Autodesk Fusion 360 part; units mm, degrees
(part 2 of 3)
extrude "Diffuser open rear skirt" add sketch "Diffuser hollow skirt outside profile" against normal blind 2.6 bodies 4
ref_plane "WorkPlane13" through (12.125, -2.4482, 27.9828) normal (0, -0.087156, 0.996195) x (1, 0, 0)
sketch "Diffuser optical cavity profile" plane through (0, -2.4482, 27.9828) normal (0, -0.087156, 0.996195) x (1, 0, 0)
  line L0 (7.7, 94.1972) -> (72.3, 94.1972)
  line L1 (72.3, 94.1972) -> (72.3, 101.7972)
  line L2 (72.3, 101.7972) -> (7.7, 101.7972)
  line L3 (7.7, 101.7972) -> (7.7, 94.1972)
  dimension "d533" = 7.7
  dimension "d534" = 94.1972
  dimension "d535" = 64.6
  dimension "d536" = 7.6
  constraint horizontal L0
  constraint vertical L1
  constraint horizontal L2
  constraint vertical L3
  measures "d533" horizontal distance of origin L0.start
  measures "d534" vertical distance of origin L0.start
  measures "d535" distance of L0.start L0.end
  measures "d536" distance of L0.end L1.end
extrude "Hollow diffuser from inside" cut sketch "Diffuser optical cavity profile" against normal blind 7 bodies 4
sketch "Diffuser right wire exit profile" plane through (0, -2.2216, 25.3927) normal (0, -0.087156, 0.996195) x (1, 0, 0)
  line L0 (71.5, 95.9972) -> (76.5, 95.9972)
  line L1 (76.5, 95.9972) -> (76.5, 99.9972)
  line L2 (76.5, 99.9972) -> (71.5, 99.9972)
  line L3 (71.5, 99.9972) -> (71.5, 95.9972)
  dimension "d539" = 71.5
  dimension "d540" = 95.9972
  dimension "d541" = 5
  dimension "d542" = 4
  constraint horizontal L0
  constraint vertical L1
  constraint horizontal L2
  constraint vertical L3
  measures "d539" horizontal distance of origin L0.start
  measures "d540" vertical distance of origin L0.start
  measures "d541" distance of L0.start L0.end
  measures "d542" distance of L0.end L1.end
extrude "Diffuser right wire exit" cut sketch "Diffuser right wire exit profile" against normal blind 6 bodies 4
sketch "Deep diffuser skirt clearance profile" plane through (0, -2.2739, 25.9904) normal (0, -0.087156, 0.996195) x (1, 0, 0)
  line L0 (5, 91.4972) -> (75, 91.4972)
  line L1 (75, 91.4972) -> (75, 104.4972)
  line L2 (75, 104.4972) -> (5, 104.4972)
  line L3 (5, 104.4972) -> (5, 91.4972)
  dimension "d545" = 5
  dimension "d546" = 91.4972
  dimension "d547" = 70
  dimension "d548" = 13
  constraint horizontal L0
  constraint vertical L1
  constraint horizontal L2
  constraint vertical L3
  measures "d545" horizontal distance of origin L0.start
  measures "d546" vertical distance of origin L0.start
  measures "d547" distance of L0.start L0.end
  measures "d548" distance of L0.end L1.end
extrude "Clear carrier around hollow diffuser" cut sketch "Deep diffuser skirt clearance profile" against normal blind 3.4 bodies 2
sketch "LED rear support web profile" plane through (0, -2.2739, 25.9904) normal (0, -0.087156, 0.996195) x (1, 0, 0)
  line L0 (6.3, 108.1799) -> (73.7, 108.1799)
  line L1 (73.7, 108.1799) -> (73.7, 112.1799)
  line L2 (73.7, 112.1799) -> (6.3, 112.1799)
  line L3 (6.3, 112.1799) -> (6.3, 108.1799)
  dimension "d551" = 6.3
  dimension "d552" = 108.1799
  dimension "d553" = 67.4
  dimension "d554" = 4
  constraint horizontal L0
  constraint vertical L1
  constraint horizontal L2
  constraint vertical L3
  measures "d551" horizontal distance of origin L0.start
  measures "d552" vertical distance of origin L0.start
  measures "d553" distance of L0.start L0.end
  measures "d554" distance of L0.end L1.end
extrude "LED rear support web" add sketch "LED rear support web profile" against normal blind 5.8 bodies 2
ref_plane "WorkPlane14" through (12.125, -1.9775, 22.6033) normal (0, -0.087156, 0.996195) x (1, 0, 0)
sketch "Continuous LED tray profile" plane through (0, -1.9775, 22.6033) normal (0, -0.087156, 0.996195) x (1, 0, 0)
  line L0 (6.3, 92.7972) -> (73.7, 92.7972)
  line L1 (73.7, 92.7972) -> (73.7, 114.4037)
  line L2 (73.7, 114.4037) -> (6.3, 114.4037)
  line L3 (6.3, 114.4037) -> (6.3, 92.7972)
  dimension "d559" = 6.3
  dimension "d560" = 92.7972
  dimension "d561" = 67.4
  dimension "d562" = 21.6065
  constraint horizontal L0
  constraint vertical L1
  constraint horizontal L2
  constraint vertical L3
  measures "d559" horizontal distance of origin L0.start
  measures "d560" vertical distance of origin L0.start
  measures "d561" distance of L0.start L0.end
  measures "d562" distance of L0.end L1.end
extrude "Continuous LED mounting crossbar" add sketch "Continuous LED tray profile" against normal blind 2.4 bodies 2
sketch "LED tray right wire relief profile" plane through (0, -1.9775, 22.6033) normal (0, -0.087156, 0.996195) x (1, 0, 0)
  line L0 (71.5, 95.9972) -> (75.5, 95.9972)
  line L1 (75.5, 95.9972) -> (75.5, 99.9972)
  line L2 (75.5, 99.9972) -> (71.5, 99.9972)
  line L3 (71.5, 99.9972) -> (71.5, 95.9972)
  dimension "d565" = 71.5
  dimension "d566" = 95.9972
  dimension "d567" = 4
  dimension "d568" = 4
  constraint horizontal L0
  constraint vertical L1
  constraint horizontal L2
  constraint vertical L3
  measures "d565" horizontal distance of origin L0.start
  measures "d566" vertical distance of origin L0.start
  measures "d567" distance of L0.start L0.end
  measures "d568" distance of L0.end L1.end
extrude "LED tray right wire relief" cut sketch "LED tray right wire relief profile" against normal blind 3.4 bodies 2
sketch "OLED seat 1 profile" plane through (0, -2.5179, 28.7797) normal (0, -0.087156, 0.996195) x (1, 0, 0)
  line L0 (5.75, 59.4972) -> (41.75, 59.4972)
  line L1 (41.75, 59.4972) -> (41.75, 62.4972)
  line L2 (41.75, 62.4972) -> (5.75, 62.4972)
  line L3 (5.75, 62.4972) -> (5.75, 59.4972)
  dimension "d571" = 5.75
  dimension "d572" = 59.4972
  dimension "d573" = 36
  dimension "d574" = 3
  constraint horizontal L0
  constraint vertical L1
  constraint horizontal L2
  constraint vertical L3
  measures "d571" horizontal distance of origin L0.start
  measures "d572" vertical distance of origin L0.start
  measures "d573" distance of L0.start L0.end
  measures "d574" distance of L0.end L1.end
extrude "OLED opposed locating ledge 1" add sketch "OLED seat 1 profile" against normal blind 2.8 bodies 1
sketch "OLED seat 2 profile" plane through (0, -2.5179, 28.7797) normal (0, -0.087156, 0.996195) x (1, 0, 0)
  line L0 (5.75, 88.4972) -> (41.75, 88.4972)
  line L1 (41.75, 88.4972) -> (41.75, 91.4972)
  line L2 (41.75, 91.4972) -> (5.75, 91.4972)
  line L3 (5.75, 91.4972) -> (5.75, 88.4972)
  dimension "d577" = 5.75
  dimension "d578" = 88.4972
  dimension "d579" = 36
  dimension "d580" = 3
  constraint horizontal L0
  constraint vertical L1
  constraint horizontal L2
  constraint vertical L3
  measures "d577" horizontal distance of origin L0.start
  measures "d578" vertical distance of origin L0.start
  measures "d579" distance of L0.start L0.end
  measures "d580" distance of L0.end L1.end
extrude "OLED opposed locating ledge 2" add sketch "OLED seat 2 profile" against normal blind 2.8 bodies 1
sketch "OLED PCB carrier clearance profile" plane through (0, -2.2739, 25.9904) normal (0, -0.087156, 0.996195) x (1, 0, 0)
  line L0 (5.55, 59.2972) -> (41.95, 59.2972)
  line L1 (41.95, 59.2972) -> (41.95, 93.6972)
  line L2 (41.95, 93.6972) -> (5.55, 93.6972)
  line L3 (5.55, 93.6972) -> (5.55, 59.2972)
  dimension "d583" = 5.55
  dimension "d584" = 59.2972
  dimension "d585" = 36.4
  dimension "d586" = 34.4
  constraint horizontal L0
  constraint vertical L1
  constraint horizontal L2
  constraint vertical L3
  measures "d583" horizontal distance of origin L0.start
  measures "d584" vertical distance of origin L0.start
  measures "d585" distance of L0.start L0.end
  measures "d586" distance of L0.end L1.end
extrude "OLED PCB clearance in carrier" cut sketch "OLED PCB carrier clearance profile" against normal blind 1.8 bodies 2
ref_plane "WorkPlane15" through (12.125, -2.117, 24.1972) normal (0, -0.087156, 0.996195) x (1, 0, 0)
sketch "OLED front clamp root profile" plane through (0, -2.2739, 25.9904) normal (0, -0.087156, 0.996195) x (1, 0, 0)
  line L0 (18, 58.4972) -> (32, 58.4972)
  line L1 (32, 58.4972) -> (32, 59.4972)
  line L2 (32, 59.4972) -> (18, 59.4972)
  line L3 (18, 59.4972) -> (18, 58.4972)
  dimension "d591" = 18
  dimension "d592" = 58.4972
  dimension "d593" = 14
  dimension "d594" = 1
  constraint horizontal L0
  constraint vertical L1
  constraint horizontal L2
  constraint vertical L3
  measures "d591" horizontal distance of origin L0.start
  measures "d592" vertical distance of origin L0.start
  measures "d593" distance of L0.start L0.end
  measures "d594" distance of L0.end L1.end
extrude "OLED front clamp root" add sketch "OLED front clamp root profile" against normal blind 3.8 bodies 2
sketch "OLED front opposed clamp profile" plane through (0, -2.117, 24.1972) normal (0, -0.087156, 0.996195) x (1, 0, 0)
  line L0 (18, 58.4972) -> (32, 58.4972)
  line L1 (32, 58.4972) -> (32, 62.4972)
  line L2 (32, 62.4972) -> (18, 62.4972)
  line L3 (18, 62.4972) -> (18, 58.4972)
  dimension "d597" = 18
  dimension "d598" = 58.4972
  dimension "d599" = 14
  dimension "d600" = 4
  constraint horizontal L0
  constraint vertical L1
  constraint horizontal L2
  constraint vertical L3
  measures "d597" horizontal distance of origin L0.start
  measures "d598" vertical distance of origin L0.start
  measures "d599" distance of L0.start L0.end
  measures "d600" distance of L0.end L1.end
extrude "OLED front opposed clamp" add sketch "OLED front opposed clamp profile" against normal blind 2 bodies 2
sketch "OLED rear clamp connecting bridge profile" plane through (0, -1.9775, 22.6033) normal (0, -0.087156, 0.996195) x (1, 0, 0)
  line L0 (18, 89.2972) -> (32, 89.2972)
  line L1 (32, 89.2972) -> (32, 93.0972)
  line L2 (32, 93.0972) -> (18, 93.0972)
  line L3 (18, 93.0972) -> (18, 89.2972)
  dimension "d603" = 18
  dimension "d604" = 89.2972
  dimension "d605" = 14
  dimension "d606" = 3.8
  constraint horizontal L0
  constraint vertical L1
  constraint horizontal L2
  constraint vertical L3
  measures "d603" horizontal distance of origin L0.start
  measures "d604" vertical distance of origin L0.start
  measures "d605" distance of L0.start L0.end
  measures "d606" distance of L0.end L1.end
extrude "OLED rear clamp connecting bridge" add sketch "OLED rear clamp connecting bridge profile" against normal blind 2.4 bodies 2
sketch "OLED rear opposed clamp profile" plane through (0, -2.117, 24.1972) normal (0, -0.087156, 0.996195) x (1, 0, 0)
  line L0 (18, 89.4972) -> (32, 89.4972)
  line L1 (32, 89.4972) -> (32, 91.4972)
  line L2 (32, 91.4972) -> (18, 91.4972)
  line L3 (18, 91.4972) -> (18, 89.4972)
  dimension "d609" = 18
  dimension "d610" = 89.4972
  dimension "d611" = 14
  dimension "d612" = 2
  constraint horizontal L0
  constraint vertical L1
  constraint horizontal L2
  constraint vertical L3
  measures "d609" horizontal distance of origin L0.start
  measures "d610" vertical distance of origin L0.start
  measures "d611" distance of L0.start L0.end
  measures "d612" distance of L0.end L1.end
extrude "OLED rear opposed clamp" add sketch "OLED rear opposed clamp profile" against normal blind 2 bodies 2
sketch "OLED PCB carrier clearance profile (1)" plane through (0, -2.2739, 25.9904) normal (0, -0.087156, 0.996195) x (1, 0, 0)
  line L0 (5.55, 59.2972) -> (41.95, 59.2972)
  line L1 (41.95, 59.2972) -> (41.95, 93.6972)
  line L2 (41.95, 93.6972) -> (5.55, 93.6972)
  line L3 (5.55, 93.6972) -> (5.55, 59.2972)
  dimension "d615" = 5.55
  dimension "d616" = 59.2972
  dimension "d617" = 36.4
  dimension "d618" = 34.4
  constraint horizontal L0
  constraint vertical L1
  constraint horizontal L2
  constraint vertical L3
  measures "d615" horizontal distance of origin L0.start
  measures "d616" vertical distance of origin L0.start
  measures "d617" distance of L0.start L0.end
  measures "d618" distance of L0.end L1.end
extrude "OLED PCB clearance in carrier (1)" cut sketch "OLED PCB carrier clearance profile (1)" against normal blind 1.8 bodies 2
ref_plane "WorkPlane16" through (0, 0, 26.3) normal (0, 0, 1) x (1, 0, 0)
sketch "PCB1 perimeter support profile" plane through (0, 0, 26.3) normal (0, 0, 1) x (1, 0, 0)
  line L0 (3.2, 62.2) -> (4.8, 62.2)
  line L1 (4.8, 62.2) -> (4.8, 66.2)
  line L2 (4.8, 66.2) -> (3.2, 66.2)
  line L3 (3.2, 66.2) -> (3.2, 62.2)
  dimension "d623" = 3.2
  dimension "d624" = 62.2
  dimension "d625" = 1.6
  dimension "d626" = 4
  constraint horizontal L0
  constraint vertical L1
  constraint horizontal L2
  constraint vertical L3
  measures "d623" horizontal distance of origin L0.start
  measures "d624" vertical distance of origin L0.start
  measures "d625" distance of L0.start L0.end
  measures "d626" distance of L0.end L1.end
sketch "PCB1 short post bridge profile" plane through (0, 0, 26.3) normal (0, 0, 1) x (1, 0, 0)
  line L0 (3.2, 62.2) -> (7, 62.2)
  line L1 (7, 62.2) -> (7, 66.2)
  line L2 (7, 66.2) -> (3.2, 66.2)
  line L3 (3.2, 66.2) -> (3.2, 62.2)
  dimension "d629" = 3.2
  dimension "d630" = 62.2
  dimension "d631" = 3.8
  dimension "d632" = 4
  constraint horizontal L0
  constraint vertical L1
  constraint horizontal L2
  constraint vertical L3
  measures "d629" horizontal distance of origin L0.start
  measures "d630" vertical distance of origin L0.start
  measures "d631" distance of L0.start L0.end
  measures "d632" distance of L0.end L1.end
sketch "PCB1 post profile" plane through (0, 0, 22.3) normal (0, 0, 1) x (1, 0, 0)
  circle A0 centre (7, 64.2) radius 2.2
  dimension "d635" = 7
  dimension "d636" = 64.2
  dimension "d637" = 4.4
  measures "d635" horizontal distance of origin A0.centre
  measures "d636" vertical distance of origin A0.centre
  measures "d637" diameter of A0
sketch "PCB1 M2 pilot profile" plane through (0, 0, 22.3) normal (0, 0, 1) x (1, 0, 0)
  circle A0 centre (7, 64.2) radius 0.85
  dimension "d640" = 7
  dimension "d641" = 64.2
  dimension "d642" = 1.7
  measures "d640" horizontal distance of origin A0.centre
  measures "d641" vertical distance of origin A0.centre
  measures "d642" diameter of A0
sketch "PCB2 perimeter support profile" plane through (0, 0, 26.3) normal (0, 0, 1) x (1, 0, 0)
  line L0 (75.2, 62.2) -> (76.8, 62.2)
  line L1 (76.8, 62.2) -> (76.8, 66.2)
  line L2 (76.8, 66.2) -> (75.2, 66.2)
  line L3 (75.2, 66.2) -> (75.2, 62.2)
  dimension "d645" = 75.2
  dimension "d646" = 62.2
  dimension "d647" = 1.6
  dimension "d648" = 4
  constraint horizontal L0
  constraint vertical L1
  constraint horizontal L2
  constraint vertical L3
  measures "d645" horizontal distance of origin L0.start
  measures "d646" vertical distance of origin L0.start
  measures "d647" distance of L0.start L0.end
  measures "d648" distance of L0.end L1.end
sketch "PCB2 short post bridge profile" plane through (0, 0, 26.3) normal (0, 0, 1) x (1, 0, 0)
  line L0 (73, 62.2) -> (76.8, 62.2)
  line L1 (76.8, 62.2) -> (76.8, 66.2)
  line L2 (76.8, 66.2) -> (73, 66.2)
  line L3 (73, 66.2) -> (73, 62.2)
  dimension "d651" = 73
  dimension "d652" = 62.2
  dimension "d653" = 3.8
  dimension "d654" = 4
  constraint horizontal L0
  constraint vertical L1
  constraint horizontal L2
  constraint vertical L3
  measures "d651" horizontal distance of origin L0.start
  measures "d652" vertical distance of origin L0.start
  measures "d653" distance of L0.start L0.end
  measures "d654" distance of L0.end L1.end
sketch "PCB2 post profile" plane through (0, 0, 22.3) normal (0, 0, 1) x (1, 0, 0)
  circle A0 centre (73, 64.2) radius 2.2
  dimension "d657" = 73
  dimension "d658" = 64.2
  dimension "d659" = 4.4
  measures "d657" horizontal distance of origin A0.centre
  measures "d658" vertical distance of origin A0.centre
  measures "d659" diameter of A0
sketch "PCB2 M2 pilot profile" plane through (0, 0, 22.3) normal (0, 0, 1) x (1, 0, 0)
  circle A0 centre (73, 64.2) radius 0.85
  dimension "d662" = 73
  dimension "d663" = 64.2
  dimension "d664" = 1.7
  measures "d662" horizontal distance of origin A0.centre
  measures "d663" vertical distance of origin A0.centre
  measures "d664" diameter of A0
sketch "PCB3 perimeter support profile" plane through (0, 0, 26.3) normal (0, 0, 1) x (1, 0, 0)
  line L0 (3.2, 108.2) -> (4.8, 108.2)
  line L1 (4.8, 108.2) -> (4.8, 112.2)
  line L2 (4.8, 112.2) -> (3.2, 112.2)
  line L3 (3.2, 112.2) -> (3.2, 108.2)
  dimension "d667" = 3.2
  dimension "d668" = 108.2
  dimension "d669" = 1.6
  dimension "d670" = 4
  constraint horizontal L0
  constraint vertical L1
  constraint horizontal L2
  constraint vertical L3
  measures "d667" horizontal distance of origin L0.start
  measures "d668" vertical distance of origin L0.start
  measures "d669" distance of L0.start L0.end
  measures "d670" distance of L0.end L1.end
sketch "PCB3 short post bridge profile" plane through (0, 0, 26.3) normal (0, 0, 1) x (1, 0, 0)
  line L0 (3.2, 108.2) -> (7, 108.2)
  line L1 (7, 108.2) -> (7, 112.2)
  line L2 (7, 112.2) -> (3.2, 112.2)
  line L3 (3.2, 112.2) -> (3.2, 108.2)
  dimension "d673" = 3.2
  dimension "d674" = 108.2
  dimension "d675" = 3.8
  dimension "d676" = 4
  constraint horizontal L0
  constraint vertical L1
  constraint horizontal L2
  constraint vertical L3
  measures "d673" horizontal distance of origin L0.start
  measures "d674" vertical distance of origin L0.start
  measures "d675" distance of L0.start L0.end
  measures "d676" distance of L0.end L1.end
sketch "PCB3 post profile" plane through (0, 0, 22.3) normal (0, 0, 1) x (1, 0, 0)
  circle A0 centre (7, 110.2) radius 2.2
  dimension "d679" = 7
  dimension "d680" = 110.2
  dimension "d681" = 4.4
  measures "d679" horizontal distance of origin A0.centre
  measures "d680" vertical distance of origin A0.centre
  measures "d681" diameter of A0
sketch "PCB3 M2 pilot profile" plane through (0, 0, 22.3) normal (0, 0, 1) x (1, 0, 0)
  circle A0 centre (7, 110.2) radius 0.85
  dimension "d684" = 7
  dimension "d685" = 110.2
  dimension "d686" = 1.7
  measures "d684" horizontal distance of origin A0.centre
  measures "d685" vertical distance of origin A0.centre
  measures "d686" diameter of A0
sketch "PCB4 perimeter support profile" plane through (0, 0, 26.3) normal (0, 0, 1) x (1, 0, 0)
  line L0 (75.2, 108.2) -> (76.8, 108.2)
  line L1 (76.8, 108.2) -> (76.8, 112.2)
  line L2 (76.8, 112.2) -> (75.2, 112.2)
  line L3 (75.2, 112.2) -> (75.2, 108.2)
  dimension "d689" = 75.2
  dimension "d690" = 108.2
  dimension "d691" = 1.6
  dimension "d692" = 4
  constraint horizontal L0
  constraint vertical L1
  constraint horizontal L2
  constraint vertical L3
  measures "d689" horizontal distance of origin L0.start
  measures "d690" vertical distance of origin L0.start
  measures "d691" distance of L0.start L0.end
  measures "d692" distance of L0.end L1.end
sketch "PCB4 short post bridge profile" plane through (0, 0, 26.3) normal (0, 0, 1) x (1, 0, 0)
  line L0 (73, 108.2) -> (76.8, 108.2)
  line L1 (76.8, 108.2) -> (76.8, 112.2)
  line L2 (76.8, 112.2) -> (73, 112.2)
  line L3 (73, 112.2) -> (73, 108.2)
  dimension "d695" = 73
  dimension "d696" = 108.2
  dimension "d697" = 3.8
  dimension "d698" = 4
  constraint horizontal L0
  constraint vertical L1
  constraint horizontal L2
  constraint vertical L3
  measures "d695" horizontal distance of origin L0.start
  measures "d696" vertical distance of origin L0.start
  measures "d697" distance of L0.start L0.end
  measures "d698" distance of L0.end L1.end
sketch "PCB4 post profile" plane through (0, 0, 22.3) normal (0, 0, 1) x (1, 0, 0)
  circle A0 centre (73, 110.2) radius 2.2
  dimension "d701" = 73
  dimension "d702" = 110.2
  dimension "d703" = 4.4
  measures "d701" horizontal distance of origin A0.centre
  measures "d702" vertical distance of origin A0.centre
  measures "d703" diameter of A0
sketch "PCB4 M2 pilot profile" plane through (0, 0, 22.3) normal (0, 0, 1) x (1, 0, 0)
  circle A0 centre (73, 110.2) radius 0.85
  dimension "d706" = 73
  dimension "d707" = 110.2
  dimension "d708" = 1.7
  measures "d706" horizontal distance of origin A0.centre
  measures "d707" vertical distance of origin A0.centre
  measures "d708" diameter of A0
ref_plane "WorkPlane17" through (12.125, -1.8381, 21.0094) normal (0, -0.087156, 0.996195) x (1, 0, 0)
sketch "M1 carrier stop profile" plane through (0, -1.8729, 21.4079) normal (0, -0.087156, 0.996195) x (1, 0, 0)
  circle A0 centre (12, 13.0275) radius 3.5
  dimension "d713" = 12
  dimension "d715" = 7
  measures "d713" horizontal distance of origin A0.centre
  measures "d715" diameter of A0
extrude "M1 rigid carrier stop" add sketch "M1 carrier stop profile" against normal blind 0.4 bodies 1
sketch "M1 stop insert entry profile" plane through (0, -1.8381, 21.0094) normal (0, -0.087156, 0.996195) x (1, 0, 0)
  circle A0 centre (12, 13.0275) radius 1.6
  dimension "d718" = 12
  dimension "d720" = 3.2
  measures "d718" horizontal distance of origin A0.centre
  measures "d720" diameter of A0
extrude "M1 open stop insert entry" cut sketch "M1 stop insert entry profile" along normal blind 0.5 bodies 1
sketch "M2 carrier stop profile" plane through (0, -1.8729, 21.4079) normal (0, -0.087156, 0.996195) x (1, 0, 0)
  circle A0 centre (68, 13.0275) radius 3.5
  dimension "d723" = 68
  dimension "d725" = 7
  measures "d723" horizontal distance of origin A0.centre
  measures "d725" diameter of A0
extrude "M2 rigid carrier stop" add sketch "M2 carrier stop profile" against normal blind 0.4 bodies 1
sketch "M2 stop insert entry profile" plane through (0, -1.8381, 21.0094) normal (0, -0.087156, 0.996195) x (1, 0, 0)
  circle A0 centre (68, 13.0275) radius 1.6
  dimension "d728" = 68
  dimension "d730" = 3.2
  measures "d728" horizontal distance of origin A0.centre
  measures "d730" diameter of A0
extrude "M2 open stop insert entry" cut sketch "M2 stop insert entry profile" along normal blind 0.5 bodies 1
sketch "M3 carrier stop profile" plane through (0, -1.8729, 21.4079) normal (0, -0.087156, 0.996195) x (1, 0, 0)
  circle A0 centre (12, 108.3268) radius 3.5
  dimension "d733" = 12
  dimension "d735" = 7
  measures "d733" horizontal distance of origin A0.centre
  measures "d735" diameter of A0
extrude "M3 rigid carrier stop" add sketch "M3 carrier stop profile" against normal blind 0.4 bodies 1
sketch "M3 stop insert entry profile" plane through (0, -1.8381, 21.0094) normal (0, -0.087156, 0.996195) x (1, 0, 0)
  circle A0 centre (12, 108.3268) radius 1.6
  dimension "d738" = 12
  dimension "d740" = 3.2
  measures "d738" horizontal distance of origin A0.centre
  measures "d740" diameter of A0
extrude "M3 open stop insert entry" cut sketch "M3 stop insert entry profile" along normal blind 0.5 bodies 1
sketch "M3 restored carrier pocket profile" plane through (0, -1.8381, 21.0094) normal (0, -0.087156, 0.996195) x (1, 0, 0)
  circle A0 centre (12, 108.3268) radius 4.2024
  dimension "d743" = 12
  dimension "d745" = 8.4049
  measures "d743" horizontal distance of origin A0.centre
  measures "d745" diameter of A0
extrude "M3 restored carrier pocket" cut sketch "M3 restored carrier pocket profile" along normal blind 7.8 bodies 2
sketch "M3 restored screw clearance profile" plane through (0, -2.2739, 25.9904) normal (0, -0.087156, 0.996195) x (1, 0, 0)
  circle A0 centre (12, 108.3268) radius 1.15
  dimension "d748" = 12
  dimension "d750" = 2.3
  measures "d748" horizontal distance of origin A0.centre
  measures "d750" diameter of A0
extrude "M3 restored screw clearance" cut sketch "M3 restored screw clearance profile" against normal blind 10 bodies 2
sketch "M3 restored cover boss relief profile" plane through (0, 0, 2) normal (0, 0, 1) x (1, 0, 0)
  circle A0 centre (20, 112) radius 3.2
  dimension "d753" = 20
  dimension "d754" = 112
  dimension "d755" = 6.4
  measures "d753" horizontal distance of origin A0.centre
  measures "d754" vertical distance of origin A0.centre
  measures "d755" diameter of A0
extrude "M3 restored cover boss relief" cut sketch "M3 restored cover boss relief profile" along normal blind 40.0612 bodies 2
sketch "M4 carrier stop profile" plane through (0, -1.8729, 21.4079) normal (0, -0.087156, 0.996195) x (1, 0, 0)
  circle A0 centre (68, 108.3268) radius 3.5
  dimension "d758" = 68
  dimension "d760" = 7
  measures "d758" horizontal distance of origin A0.centre
  measures "d760" diameter of A0
extrude "M4 rigid carrier stop" add sketch "M4 carrier stop profile" against normal blind 0.4 bodies 1
sketch "M4 stop insert entry profile" plane through (0, -1.8381, 21.0094) normal (0, -0.087156, 0.996195) x (1, 0, 0)
  circle A0 centre (68, 108.3268) radius 1.6
  dimension "d763" = 68
  dimension "d765" = 3.2
  measures "d763" horizontal distance of origin A0.centre
  measures "d765" diameter of A0
extrude "M4 open stop insert entry" cut sketch "M4 stop insert entry profile" along normal blind 0.5 bodies 1
sketch "M4 restored carrier pocket profile" plane through (0, -1.8381, 21.0094) normal (0, -0.087156, 0.996195) x (1, 0, 0)
  circle A0 centre (68, 108.3268) radius 4.2024
  dimension "d768" = 68
  dimension "d770" = 8.4049
  measures "d768" horizontal distance of origin A0.centre
  measures "d770" diameter of A0
extrude "M4 restored carrier pocket" cut sketch "M4 restored carrier pocket profile" along normal blind 7.8 bodies 2
sketch "M4 restored screw clearance profile" plane through (0, -2.2739, 25.9904) normal (0, -0.087156, 0.996195) x (1, 0, 0)
  circle A0 centre (68, 108.3268) radius 1.15
  dimension "d773" = 68
  dimension "d775" = 2.3
  measures "d773" horizontal distance of origin A0.centre
  measures "d775" diameter of A0
extrude "M4 restored screw clearance" cut sketch "M4 restored screw clearance profile" against normal blind 10 bodies 2
sketch "M4 restored cover boss relief profile" plane through (0, 0, 2) normal (0, 0, 1) x (1, 0, 0)
  circle A0 centre (60, 112) radius 3.2
  dimension "d778" = 60
  dimension "d779" = 112
  dimension "d780" = 6.4
  measures "d778" horizontal distance of origin A0.centre
  measures "d779" vertical distance of origin A0.centre
  measures "d780" diameter of A0
extrude "M4 restored cover boss relief" cut sketch "M4 restored cover boss relief profile" along normal blind 40.0612 bodies 2
ref_plane "WorkPlane18" through (3.2, 0, 0) normal (1, 0, 0) x (0, 1, 0)
sketch "PCB direct rail 1 profile" plane through (3.2, 0, 0) normal (1, 0, 0) x (0, 0, -1)
  line L0 (-27.8, 62.2) -> (-27.8, 112.2)
  line L1 (-27.8, 112.2) -> (-34.8009, 112.2)
  line L2 (-34.8009, 112.2) -> (-30.4265, 62.2)
  line L3 (-30.4265, 62.2) -> (-27.8, 62.2)
  dimension "d788" = 27.8
  dimension "d789" = 62.2
  dimension "d790" = 50
  dimension "d791" = 7.0009
  dimension "d792" = 2.6265
  constraint vertical L0
  constraint horizontal L1
  constraint horizontal L3
  measures "d788" horizontal distance of origin L0.start
  measures "d789" vertical distance of origin L0.start
  measures "d790" distance of L0.start L0.end
  measures "d791" distance of L0.end L1.end
  measures "d792" distance of L0.start L2.end
extrude "PCB direct rail 1" add sketch "PCB direct rail 1 profile" along normal blind 1.6 bodies 2
ref_plane "WorkPlane19" through (75.2, 0, 0) normal (1, 0, 0) x (0, 1, 0)
sketch "PCB direct rail 2 profile" plane through (75.2, 0, 0) normal (1, 0, 0) x (0, 0, -1)
  line L0 (-27.8, 62.2) -> (-27.8, 112.2)
  line L1 (-27.8, 112.2) -> (-34.8009, 112.2)
  line L2 (-34.8009, 112.2) -> (-30.4265, 62.2)
  line L3 (-30.4265, 62.2) -> (-27.8, 62.2)
  dimension "d797" = 27.8
  dimension "d798" = 62.2
  dimension "d799" = 50
  dimension "d800" = 7.0009
  dimension "d801" = 2.6265
  constraint vertical L0
  constraint horizontal L1
  constraint horizontal L3
  measures "d797" horizontal distance of origin L0.start
  measures "d798" vertical distance of origin L0.start
  measures "d799" distance of L0.start L0.end
  measures "d800" distance of L0.end L1.end
  measures "d801" distance of L0.start L2.end
extrude "PCB direct rail 2" add sketch "PCB direct rail 2 profile" along normal blind 1.6 bodies 2
ref_plane "WorkPlane20" through (0, 0, 27.8) normal (0, 0, 1) x (1, 0, 0)
sketch "PCB direct mount 1 ear profile" plane through (0, 0, 27.8) normal (0, 0, 1) x (1, 0, 0)
  line L0 (3.2, 62) -> (9.2, 62)
  line L1 (9.2, 62) -> (9.2, 66.4)
  line L2 (9.2, 66.4) -> (3.2, 66.4)
  line L3 (3.2, 66.4) -> (3.2, 62)
  dimension "d806" = 3.2
  dimension "d807" = 62
  dimension "d808" = 6
  dimension "d809" = 4.4
  constraint horizontal L0
  constraint vertical L1
  constraint horizontal L2
  constraint vertical L3
  measures "d806" horizontal distance of origin L0.start
  measures "d807" vertical distance of origin L0.start
  measures "d808" distance of L0.start L0.end
  measures "d809" distance of L0.end L1.end
extrude "PCB direct mount 1 ear" add sketch "PCB direct mount 1 ear profile" along normal blind 1.5 bodies 2
sketch "PCB direct mount 1 boss profile" plane through (0, 0, 22.3) normal (0, 0, 1) x (1, 0, 0)
  circle A0 centre (7, 64.2) radius 2.2
  dimension "d812" = 7
  dimension "d813" = 64.2
  dimension "d814" = 4.4
  measures "d812" horizontal distance of origin A0.centre
  measures "d813" vertical distance of origin A0.centre
  measures "d814" diameter of A0
extrude "PCB direct mount 1 boss" add sketch "PCB direct mount 1 boss profile" along normal blind 7 bodies 2
sketch "PCB direct mount 1 screw profile" plane through (0, 0, 22.3) normal (0, 0, 1) x (1, 0, 0)
  circle A0 centre (7, 64.2) radius 0.85
  dimension "d817" = 7
  dimension "d818" = 64.2
  dimension "d819" = 1.7
  measures "d817" horizontal distance of origin A0.centre
  measures "d818" vertical distance of origin A0.centre
  measures "d819" diameter of A0
extrude "PCB direct mount 1 screw pilot" cut sketch "PCB direct mount 1 screw profile" along normal blind 4.5 bodies 2
sketch "PCB direct mount 2 ear profile" plane through (0, 0, 27.8) normal (0, 0, 1) x (1, 0, 0)
  line L0 (70.8, 62) -> (76.8, 62)
  line L1 (76.8, 62) -> (76.8, 66.4)
  line L2 (76.8, 66.4) -> (70.8, 66.4)
  line L3 (70.8, 66.4) -> (70.8, 62)
  dimension "d822" = 70.8
  dimension "d823" = 62
  dimension "d824" = 6
  dimension "d825" = 4.4
  constraint horizontal L0
  constraint vertical L1
  constraint horizontal L2
  constraint vertical L3
  measures "d822" horizontal distance of origin L0.start
  measures "d823" vertical distance of origin L0.start
  measures "d824" distance of L0.start L0.end
  measures "d825" distance of L0.end L1.end
extrude "PCB direct mount 2 ear" add sketch "PCB direct mount 2 ear profile" along normal blind 1.5 bodies 2
sketch "PCB direct mount 2 boss profile" plane through (0, 0, 22.3) normal (0, 0, 1) x (1, 0, 0)
  circle A0 centre (73, 64.2) radius 2.2
  dimension "d828" = 73
  dimension "d829" = 64.2
  dimension "d830" = 4.4
  measures "d828" horizontal distance of origin A0.centre
  measures "d829" vertical distance of origin A0.centre
  measures "d830" diameter of A0
extrude "PCB direct mount 2 boss" add sketch "PCB direct mount 2 boss profile" along normal blind 7 bodies 2
sketch "PCB direct mount 2 screw profile" plane through (0, 0, 22.3) normal (0, 0, 1) x (1, 0, 0)
  circle A0 centre (73, 64.2) radius 0.85
  dimension "d833" = 73
  dimension "d834" = 64.2
  dimension "d835" = 1.7
  measures "d833" horizontal distance of origin A0.centre
  measures "d834" vertical distance of origin A0.centre
  measures "d835" diameter of A0
extrude "PCB direct mount 2 screw pilot" cut sketch "PCB direct mount 2 screw profile" along normal blind 4.5 bodies 2
sketch "PCB direct mount 3 ear profile" plane through (0, 0, 27.8) normal (0, 0, 1) x (1, 0, 0)
  line L0 (3.2, 108) -> (9.2, 108)
  line L1 (9.2, 108) -> (9.2, 112.4)
  line L2 (9.2, 112.4) -> (3.2, 112.4)
  line L3 (3.2, 112.4) -> (3.2, 108)
  dimension "d838" = 3.2
  dimension "d839" = 108
  dimension "d840" = 6
  dimension "d841" = 4.4
  constraint horizontal L0
  constraint vertical L1
  constraint horizontal L2
  constraint vertical L3
  measures "d838" horizontal distance of origin L0.start
  measures "d839" vertical distance of origin L0.start
  measures "d840" distance of L0.start L0.end
  measures "d841" distance of L0.end L1.end
extrude "PCB direct mount 3 ear" add sketch "PCB direct mount 3 ear profile" along normal blind 1.5 bodies 2
sketch "PCB direct mount 3 boss profile" plane through (0, 0, 22.3) normal (0, 0, 1) x (1, 0, 0)
  circle A0 centre (7, 110.2) radius 2.2
  dimension "d844" = 7
  dimension "d845" = 110.2
  dimension "d846" = 4.4
  measures "d844" horizontal distance of origin A0.centre
  measures "d845" vertical distance of origin A0.centre
  measures "d846" diameter of A0
extrude "PCB direct mount 3 boss" add sketch "PCB direct mount 3 boss profile" along normal blind 7 bodies 2
sketch "PCB direct mount 3 screw profile" plane through (0, 0, 22.3) normal (0, 0, 1) x (1, 0, 0)
  circle A0 centre (7, 110.2) radius 0.85
  dimension "d849" = 7
  dimension "d850" = 110.2
  dimension "d851" = 1.7
  measures "d849" horizontal distance of origin A0.centre
  measures "d850" vertical distance of origin A0.centre
  measures "d851" diameter of A0
extrude "PCB direct mount 3 screw pilot" cut sketch "PCB direct mount 3 screw profile" along normal blind 4.5 bodies 2
sketch "PCB direct mount 4 ear profile" plane through (0, 0, 27.8) normal (0, 0, 1) x (1, 0, 0)
  line L0 (70.8, 108) -> (76.8, 108)
  line L1 (76.8, 108) -> (76.8, 112.4)
  line L2 (76.8, 112.4) -> (70.8, 112.4)
  line L3 (70.8, 112.4) -> (70.8, 108)
  dimension "d854" = 70.8
  dimension "d855" = 108
  dimension "d856" = 6
  dimension "d857" = 4.4
  constraint horizontal L0
  constraint vertical L1
  constraint horizontal L2
  constraint vertical L3
  measures "d854" horizontal distance of origin L0.start
  measures "d855" vertical distance of origin L0.start
  measures "d856" distance of L0.start L0.end
  measures "d857" distance of L0.end L1.end
extrude "PCB direct mount 4 ear" add sketch "PCB direct mount 4 ear profile" along normal blind 1.5 bodies 2
sketch "PCB direct mount 4 boss profile" plane through (0, 0, 22.3) normal (0, 0, 1) x (1, 0, 0)
  circle A0 centre (73, 110.2) radius 2.2
  dimension "d860" = 73
  dimension "d861" = 110.2
  dimension "d862" = 4.4
  measures "d860" horizontal distance of origin A0.centre
  measures "d861" vertical distance of origin A0.centre
  measures "d862" diameter of A0
extrude "PCB direct mount 4 boss" add sketch "PCB direct mount 4 boss profile" along normal blind 7 bodies 2
sketch "PCB direct mount 4 screw profile" plane through (0, 0, 22.3) normal (0, 0, 1) x (1, 0, 0)
  circle A0 centre (73, 110.2) radius 0.85
  dimension "d865" = 73
  dimension "d866" = 110.2
  dimension "d867" = 1.7
  measures "d865" horizontal distance of origin A0.centre
  measures "d866" vertical distance of origin A0.centre
  measures "d867" diameter of A0
extrude "PCB direct mount 4 screw pilot" cut sketch "PCB direct mount 4 screw profile" along normal blind 4.5 bodies 2
equation "caseWidth = 80 mm" comment "Exterior width"
equation "caseLength = 115 mm" comment "Horizontal front-to-rear footprint"
equation "caseTilt = 5 deg" comment "Rear-up face angle; provisional"
equation "frontHeight = 29 mm" comment "Draft height, to be checked against electronics"
equation "rearHeight = frontHeight + caseLength * tan(caseTilt)" comment "Rear height"
equation "shellWall = 2.4 mm" comment "Draft shell thickness"
equation "bottomThickness = 2 mm" comment "Service cover thickness"
equation "carrierThickness = 1.5 mm" comment "Local switch clip seating thickness"
equation "carrierClearance = 0.4 mm" comment "Draft carrier clearance"
equation "carrierRim = 7 mm" comment "Carrier frame width"
equation "keycapSize = 18 mm" comment "Confirmed square keycap size"
equation "layoutGap = ( caseWidth - 3 * keycapSize ) / 4" comment "Equal visible horizontal gaps"
equation "keyPitch = keycapSize + layoutGap" comment "Equal row and column pitch"
equation "switchOpening = 14.1 mm" comment "Draft opening; coupon verification required"
equation "upperSwitchOpening = 16.2 mm" comment "Draft outer trim clearance"
equation "displayWidth = 34.5 mm" comment "User-supplied window width"
equation "displayHeight = 18.5 mm" comment "User-supplied window height"
equation "encoderKnobDiameter = 20 mm" comment "Placeholder; actual knob diameter required"
equation "encoderHole = 7 mm" comment "User-supplied provisional opening; verify bushing"
equation "ledWidth = 67 mm" comment "User-supplied strip width"
equation "ledHeight = 10 mm" comment "Initial diffuser opening height"
equation "diffuserClearance = 0.2 mm" comment "Per-edge draft fit clearance"
equation "diffuserFlange = 1.5 mm" comment "Retaining flange extension per side"
equation "diffuserFlangeThickness = 1 mm" comment "Retaining flange thickness"
equation "faceLength = caseLength / cos(caseTilt)" comment "Length measured in the inclined face"
equation "faceOriginV = frontHeight * sin(caseTilt)" comment "Inclined sketch origin correction"
equation "controlHeight = max(displayHeight; encoderKnobDiameter)" comment "Visible controls row height"
equation "contentLength = 2 * keycapSize + 3 * layoutGap + controlHeight + ledHeight" comment "Visible layout stack"
equation "verticalMargin = ( faceLength - contentLength ) / 2" comment "Balanced front and rear margins"
equation "keyRowOne = verticalMargin + keycapSize / 2" comment "Front key row center"
equation "keyRowTwo = keyRowOne + keyPitch" comment "Rear key row center"
equation "controlCenter = keyRowTwo + keycapSize / 2 + layoutGap + controlHeight / 2" comment "Display and encoder center"
equation "ledCenter = controlCenter + controlHeight / 2 + layoutGap + ledHeight / 2" comment "LED opening center"
equation "encoderCenterX = ( layoutGap + displayWidth + caseWidth ) / 2" comment "Centered in the area right of the display"
equation "d39 = -( ( 0 ) * ( 0 mm ) + ( -1 ) * ( bottomThickness ) )"
equation "d40 = ( ( 1 ) * ( caseLength ) + ( 0 ) * ( bottomThickness ) ) - ( ( 1 ) * ( 0 mm ) + ( 0 ) * ( bottomThickness ) )"
equation "d41 = -( ( ( 0 ) * ( caseLength ) + ( -1 ) * ( rearHeight ) ) - ( ( 0 ) * ( caseLength ) + ( -1 ) * ( bottomThickness ) ) )"
equation "d42 = ( ( 0 ) * ( 0 mm ) + ( -1 ) * ( bottomThickness ) ) - ( ( 0 ) * ( 0 mm ) + ( -1 ) * ( frontHeight ) )"
equation "d43 = caseWidth"
equation "d45 = shellWall"
equation "d46 = caseTilt"
equation "d48 = frontHeight * cos(caseTilt)"
equation "d50 = -( shellWall + carrierClearance )"
equation "d52 = shellWall + carrierClearance"
equation "d53 = ( ( shellWall + carrierClearance ) / cos(caseTilt) - ( shellWall + carrierClearance ) * tan(caseTilt) ) + faceOriginV"
equation "d54 = ( ( shellWall + carrierClearance ) + ( caseWidth - 2 * ( shellWall + carrierClearance ) ) ) - ( shellWall + carrierClearance )"
equation "d55 = carrierFaceLength"
equation "d56 = -( carrierThickness )"
equation "d58 = ( caseWidth - carrierBayWidth ) / 2"
equation "d59 = ( keyRowTwo + keycapSize / 2 + layoutGap / 2 ) + faceOriginV"
equation "d60 = carrierBayWidth"
equation "d61 = faceLength - ( shellWall + carrierClearance ) / cos(caseTilt) - ( shellWall + carrierClearance + carrierThickness ) * tan(caseTilt) - carrierRim - ( keyRowTwo + keycapSize / 2 + layoutGap / 2 )"
equation "d62 = -( carrierThickness + 1 mm )"
equation "d64 = ( layoutGap + keycapSize / 2 + 0 * keyPitch ) - switchOpening / 2"
equation "d65 = ( ( keyRowOne ) - switchOpening / 2 ) + faceOriginV"
equation "d66 = ( ( ( layoutGap + keycapSize / 2 + 0 * keyPitch ) - switchOpening / 2 ) + ( switchOpening ) ) - ( ( layoutGap + keycapSize / 2 + 0 * keyPitch ) - switchOpening / 2 )"
equation "d67 = ( ( ( ( keyRowOne ) - switchOpening / 2 ) + faceOriginV ) + ( switchOpening ) ) - ( ( ( keyRowOne ) - switchOpening / 2 ) + faceOriginV )"
equation "d68 = -( carrierThickness + 1 mm )"
equation "d70 = ( layoutGap + keycapSize / 2 + 0 * keyPitch ) - upperSwitchOpening / 2"
equation "d71 = ( ( keyRowOne ) - upperSwitchOpening / 2 ) + faceOriginV"
equation "d72 = ( ( ( layoutGap + keycapSize / 2 + 0 * keyPitch ) - upperSwitchOpening / 2 ) + ( upperSwitchOpening ) ) - ( ( layoutGap + keycapSize / 2 + 0 * keyPitch ) - upperSwitchOpening / 2 )"
equation "d73 = ( ( ( ( keyRowOne ) - upperSwitchOpening / 2 ) + faceOriginV ) + ( upperSwitchOpening ) ) - ( ( ( keyRowOne ) - upperSwitchOpening / 2 ) + faceOriginV )"
equation "d74 = -( shellWall + 1 mm )"
equation "d76 = ( layoutGap + keycapSize / 2 + 1 * keyPitch ) - switchOpening / 2"
equation "d77 = ( ( keyRowOne ) - switchOpening / 2 ) + faceOriginV"
equation "d78 = ( ( ( layoutGap + keycapSize / 2 + 1 * keyPitch ) - switchOpening / 2 ) + ( switchOpening ) ) - ( ( layoutGap + keycapSize / 2 + 1 * keyPitch ) - switchOpening / 2 )"
equation "d79 = ( ( ( ( keyRowOne ) - switchOpening / 2 ) + faceOriginV ) + ( switchOpening ) ) - ( ( ( keyRowOne ) - switchOpening / 2 ) + faceOriginV )"
equation "d80 = -( carrierThickness + 1 mm )"
equation "d82 = ( layoutGap + keycapSize / 2 + 1 * keyPitch ) - upperSwitchOpening / 2"
equation "d83 = ( ( keyRowOne ) - upperSwitchOpening / 2 ) + faceOriginV"
equation "d84 = ( ( ( layoutGap + keycapSize / 2 + 1 * keyPitch ) - upperSwitchOpening / 2 ) + ( upperSwitchOpening ) ) - ( ( layoutGap + keycapSize / 2 + 1 * keyPitch ) - upperSwitchOpening / 2 )"
equation "d85 = ( ( ( ( keyRowOne ) - upperSwitchOpening / 2 ) + faceOriginV ) + ( upperSwitchOpening ) ) - ( ( ( keyRowOne ) - upperSwitchOpening / 2 ) + faceOriginV )"
equation "d86 = -( shellWall + 1 mm )"
equation "d88 = ( layoutGap + keycapSize / 2 + 2 * keyPitch ) - switchOpening / 2"
equation "d89 = ( ( keyRowOne ) - switchOpening / 2 ) + faceOriginV"
equation "d90 = ( ( ( layoutGap + keycapSize / 2 + 2 * keyPitch ) - switchOpening / 2 ) + ( switchOpening ) ) - ( ( layoutGap + keycapSize / 2 + 2 * keyPitch ) - switchOpening / 2 )"
equation "d91 = ( ( ( ( keyRowOne ) - switchOpening / 2 ) + faceOriginV ) + ( switchOpening ) ) - ( ( ( keyRowOne ) - switchOpening / 2 ) + faceOriginV )"
equation "d92 = -( carrierThickness + 1 mm )"
equation "d94 = ( layoutGap + keycapSize / 2 + 2 * keyPitch ) - upperSwitchOpening / 2"
equation "d95 = ( ( keyRowOne ) - upperSwitchOpening / 2 ) + faceOriginV"
equation "d96 = ( ( ( layoutGap + keycapSize / 2 + 2 * keyPitch ) - upperSwitchOpening / 2 ) + ( upperSwitchOpening ) ) - ( ( layoutGap + keycapSize / 2 + 2 * keyPitch ) - upperSwitchOpening / 2 )"
equation "d97 = ( ( ( ( keyRowOne ) - upperSwitchOpening / 2 ) + faceOriginV ) + ( upperSwitchOpening ) ) - ( ( ( keyRowOne ) - upperSwitchOpening / 2 ) + faceOriginV )"
equation "d98 = -( shellWall + 1 mm )"
equation "d100 = ( layoutGap + keycapSize / 2 + 0 * keyPitch ) - switchOpening / 2"
equation "d101 = ( ( keyRowTwo ) - switchOpening / 2 ) + faceOriginV"
equation "d102 = ( ( ( layoutGap + keycapSize / 2 + 0 * keyPitch ) - switchOpening / 2 ) + ( switchOpening ) ) - ( ( layoutGap + keycapSize / 2 + 0 * keyPitch ) - switchOpening / 2 )"
equation "d103 = ( ( ( ( keyRowTwo ) - switchOpening / 2 ) + faceOriginV ) + ( switchOpening ) ) - ( ( ( keyRowTwo ) - switchOpening / 2 ) + faceOriginV )"
equation "d104 = -( carrierThickness + 1 mm )"
equation "d106 = ( layoutGap + keycapSize / 2 + 0 * keyPitch ) - upperSwitchOpening / 2"
equation "d107 = ( ( keyRowTwo ) - upperSwitchOpening / 2 ) + faceOriginV"
equation "d108 = ( ( ( layoutGap + keycapSize / 2 + 0 * keyPitch ) - upperSwitchOpening / 2 ) + ( upperSwitchOpening ) ) - ( ( layoutGap + keycapSize / 2 + 0 * keyPitch ) - upperSwitchOpening / 2 )"
equation "d109 = ( ( ( ( keyRowTwo ) - upperSwitchOpening / 2 ) + faceOriginV ) + ( upperSwitchOpening ) ) - ( ( ( keyRowTwo ) - upperSwitchOpening / 2 ) + faceOriginV )"
equation "d110 = -( shellWall + 1 mm )"
equation "d112 = ( layoutGap + keycapSize / 2 + 1 * keyPitch ) - switchOpening / 2"
equation "d113 = ( ( keyRowTwo ) - switchOpening / 2 ) + faceOriginV"
equation "d114 = ( ( ( layoutGap + keycapSize / 2 + 1 * keyPitch ) - switchOpening / 2 ) + ( switchOpening ) ) - ( ( layoutGap + keycapSize / 2 + 1 * keyPitch ) - switchOpening / 2 )"
equation "d115 = ( ( ( ( keyRowTwo ) - switchOpening / 2 ) + faceOriginV ) + ( switchOpening ) ) - ( ( ( keyRowTwo ) - switchOpening / 2 ) + faceOriginV )"
equation "d116 = -( carrierThickness + 1 mm )"
equation "d118 = ( layoutGap + keycapSize / 2 + 1 * keyPitch ) - upperSwitchOpening / 2"
equation "d119 = ( ( keyRowTwo ) - upperSwitchOpening / 2 ) + faceOriginV"
equation "d120 = ( ( ( layoutGap + keycapSize / 2 + 1 * keyPitch ) - upperSwitchOpening / 2 ) + ( upperSwitchOpening ) ) - ( ( layoutGap + keycapSize / 2 + 1 * keyPitch ) - upperSwitchOpening / 2 )"
equation "d121 = ( ( ( ( keyRowTwo ) - upperSwitchOpening / 2 ) + faceOriginV ) + ( upperSwitchOpening ) ) - ( ( ( keyRowTwo ) - upperSwitchOpening / 2 ) + faceOriginV )"
equation "d122 = -( shellWall + 1 mm )"
equation "d124 = ( layoutGap + keycapSize / 2 + 2 * keyPitch ) - switchOpening / 2"
equation "d125 = ( ( keyRowTwo ) - switchOpening / 2 ) + faceOriginV"
equation "d126 = ( ( ( layoutGap + keycapSize / 2 + 2 * keyPitch ) - switchOpening / 2 ) + ( switchOpening ) ) - ( ( layoutGap + keycapSize / 2 + 2 * keyPitch ) - switchOpening / 2 )"
equation "d127 = ( ( ( ( keyRowTwo ) - switchOpening / 2 ) + faceOriginV ) + ( switchOpening ) ) - ( ( ( keyRowTwo ) - switchOpening / 2 ) + faceOriginV )"
equation "d128 = -( carrierThickness + 1 mm )"
equation "d130 = ( layoutGap + keycapSize / 2 + 2 * keyPitch ) - upperSwitchOpening / 2"
equation "d131 = ( ( keyRowTwo ) - upperSwitchOpening / 2 ) + faceOriginV"
equation "d132 = ( ( ( layoutGap + keycapSize / 2 + 2 * keyPitch ) - upperSwitchOpening / 2 ) + ( upperSwitchOpening ) ) - ( ( layoutGap + keycapSize / 2 + 2 * keyPitch ) - upperSwitchOpening / 2 )"
equation "d133 = ( ( ( ( keyRowTwo ) - upperSwitchOpening / 2 ) + faceOriginV ) + ( upperSwitchOpening ) ) - ( ( ( keyRowTwo ) - upperSwitchOpening / 2 ) + faceOriginV )"
equation "d134 = -( shellWall + 1 mm )"
equation "d136 = ( caseWidth - ledWidth ) / 2"
equation "d137 = ( ledCenter - ledHeight / 2 ) + faceOriginV"
equation "d138 = ( ( ( caseWidth - ledWidth ) / 2 ) + ( ledWidth ) ) - ( ( caseWidth - ledWidth ) / 2 )"
equation "d139 = ( ( ( ledCenter - ledHeight / 2 ) + faceOriginV ) + ( ledHeight ) ) - ( ( ledCenter - ledHeight / 2 ) + faceOriginV )"
equation "d140 = -( shellWall + 1 mm )"
equation "d142 = layoutGap"
equation "d143 = ( controlCenter - displayHeight / 2 ) + faceOriginV"
equation "d144 = ( ( layoutGap ) + ( displayWidth ) ) - ( layoutGap )"
equation "d145 = ( ( ( controlCenter - displayHeight / 2 ) + faceOriginV ) + ( displayHeight ) ) - ( ( controlCenter - displayHeight / 2 ) + faceOriginV )"
equation "d146 = -( shellWall + 1 mm )"
equation "d148 = encoderCenterX"
equation "d149 = controlCenter + faceOriginV"
equation "d150 = encoderHole"
equation "d151 = -( shellWall + 1 mm )"
equation "d153 = ( ( 0 mm ) + ( caseWidth ) ) - ( 0 mm )"
equation "d154 = ( ( 0 mm ) + ( caseLength ) ) - ( 0 mm )"
equation "d155 = bottomThickness"
equation "d157 = ( caseWidth - ledWidth ) / 2 + diffuserClearance"
equation "d158 = ( ledCenter - ledHeight / 2 + diffuserClearance ) + faceOriginV"
equation "d159 = ( ( ( caseWidth - ledWidth ) / 2 + diffuserClearance ) + ( ledWidth - 2 * diffuserClearance ) ) - ( ( caseWidth - ledWidth ) / 2 + diffuserClearance )"
equation "d160 = ( ( ( ledCenter - ledHeight / 2 + diffuserClearance ) + faceOriginV ) + ( ledHeight - 2 * diffuserClearance ) ) - ( ( ledCenter - ledHeight / 2 + diffuserClearance ) + faceOriginV )"
equation "d161 = -( shellWall )"
equation "d163 = -shellWall"
equation "d165 = ( caseWidth - ledWidth ) / 2 + diffuserClearance - diffuserFlange"
equation "d166 = ( ledCenter - ledHeight / 2 + diffuserClearance - diffuserFlange ) + faceOriginV"
equation "d167 = ( ( ( caseWidth - ledWidth ) / 2 + diffuserClearance - diffuserFlange ) + ( ledWidth - 2 * diffuserClearance + 2 * diffuserFlange ) ) - ( ( caseWidth - ledWidth ) / 2 + diffuserClearance - diffuserFlange )"
equation "d168 = ( ( ( ledCenter - ledHeight / 2 + diffuserClearance - diffuserFlange ) + faceOriginV ) + ( ledHeight - 2 * diffuserClearance + 2 * diffuserFlange ) ) - ( ( ledCenter - ledHeight / 2 + diffuserClearance - diffuserFlange ) + faceOriginV )"
equation "d169 = -( diffuserFlangeThickness )"
equation "carrierFaceLength = faceLength - 2 * ( shellWall + carrierClearance ) / cos(caseTilt) - carrierThickness * tan(caseTilt)" comment "Carrier rear clearance"
equation "d172 = layoutGap + 0 * keyPitch"
equation "d173 = ( keyRowOne - keycapSize / 2 ) + faceOriginV"
equation "d174 = ( ( layoutGap + 0 * keyPitch ) + ( keycapSize ) ) - ( layoutGap + 0 * keyPitch )"
equation "d175 = ( ( ( keyRowOne - keycapSize / 2 ) + faceOriginV ) + ( keycapSize ) ) - ( ( keyRowOne - keycapSize / 2 ) + faceOriginV )"
equation "d176 = layoutGap + 1 * keyPitch"
equation "d177 = ( keyRowOne - keycapSize / 2 ) + faceOriginV"
equation "d178 = ( ( layoutGap + 1 * keyPitch ) + ( keycapSize ) ) - ( layoutGap + 1 * keyPitch )"
equation "d179 = ( ( ( keyRowOne - keycapSize / 2 ) + faceOriginV ) + ( keycapSize ) ) - ( ( keyRowOne - keycapSize / 2 ) + faceOriginV )"
equation "d180 = layoutGap + 2 * keyPitch"
equation "d181 = ( keyRowOne - keycapSize / 2 ) + faceOriginV"
equation "d182 = ( ( layoutGap + 2 * keyPitch ) + ( keycapSize ) ) - ( layoutGap + 2 * keyPitch )"
equation "d183 = ( ( ( keyRowOne - keycapSize / 2 ) + faceOriginV ) + ( keycapSize ) ) - ( ( keyRowOne - keycapSize / 2 ) + faceOriginV )"
equation "d184 = layoutGap + 0 * keyPitch"
equation "d185 = ( keyRowTwo - keycapSize / 2 ) + faceOriginV"
equation "d186 = ( ( layoutGap + 0 * keyPitch ) + ( keycapSize ) ) - ( layoutGap + 0 * keyPitch )"
equation "d187 = ( ( ( keyRowTwo - keycapSize / 2 ) + faceOriginV ) + ( keycapSize ) ) - ( ( keyRowTwo - keycapSize / 2 ) + faceOriginV )"
equation "d188 = layoutGap + 1 * keyPitch"
equation "d189 = ( keyRowTwo - keycapSize / 2 ) + faceOriginV"